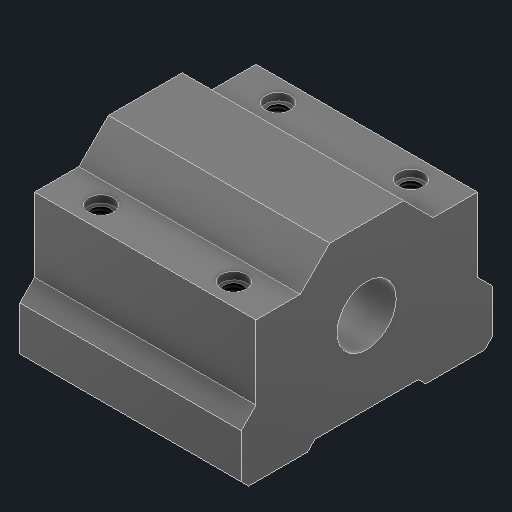
# Autodesk Inventor part: LeadWay
Saved by Autodesk Inventor 2026.2 (Build 302298000, 298)
## iProperties
Created: 2025-11-15
Part Number: LeadWay
Material: ABS 플라스틱
Document SubType Name: Modeling
Designer: work
Density: 1.06 g/cm^3
Appearance: 매끄러움 - 검은색
Author: work
Autodesk Inventor part; units mm, degrees
ref_plane "YZ Plane" through (0, 0, 0) normal (1, 0, 0) x (0, 1, 0)
ref_plane "XZ Plane" through (0, 0, 0) normal (0, 1, 0) x (-1, 0, 0)
ref_plane "XY Plane" through (0, 0, 0) normal (0, 0, 1) x (1, 0, 0)
sketch "스케치1" plane through (0, 0, 0) normal (1, 0, 0) x (0, 1, 0)
  line L0 (0, 0) -> (22, 0) construction
  line L1 (0, 0) -> (0, -17)
  line L2 (0, -17) -> (6, -17)
  line L3 (6, -17) -> (8, -15)
  line L4 (8, -15) -> (18, -15)
  line L5 (18, -15) -> (18, -9)
  line L6 (18, -9) -> (22, -5)
  line L7 (22, -5) -> (22, 0)
  circle A0 centre (11, 0) radius 4
  line L8 (18, -12) -> (0, -12) construction
  line L9 (0, -7) -> (-1, -8)
  line L10 (-1, -8) -> (-1, -16)
  line L11 (-1, -16) -> (0, -17)
  line L12 (-1, -12) -> (0, -12) construction
  line L13 (0, 0) -> (0, 17)
  line L14 (0, 17) -> (6, 17)
  line L15 (6, 17) -> (8, 15)
  line L16 (8, 15) -> (18, 15)
  line L17 (18, 15) -> (18, 9)
  line L18 (18, 9) -> (22, 5)
  line L19 (22, 5) -> (22, 0)
  line L20 (18, 12) -> (0, 12) construction
  line L21 (0, 7) -> (-1, 8)
  line L22 (-1, 8) -> (-1, 16)
  line L23 (-1, 16) -> (0, 17)
  line L24 (-1, 12) -> (0, 12) construction
  point P0 (22, -2.5)
  dimension "d0" = 22
  dimension "d1" = 6
  dimension "d2" = 8
  dimension "d3" = 18
  dimension "d4" = 8
  dimension "d5" = 17
  dimension "d6" = 5
  dimension "d7" = 135
  dimension "d8" = 135
  dimension "d9" = 45
  dimension "d10" = 45
  dimension "d11" = 1
  constraints: 50 end point, 12 symmetric about line, 4 midpoint, 4 perpendicular, 4 point on line, 3 vertical, 1 centre point, 1 horizontal, 1 parallel
  measures "d0" distance of L0.start L0.end
  measures "d1" distance of L1.end L2.end
  measures "d2" horizontal distance of L1.end L3.end
  measures "d3" distance between parallel lines of L1 L5
  measures "d4" diameter of A0
  measures "d5" distance of L0.start L1.end
  measures "d6" distance between parallel lines of L2 L8
  measures "d7" angle of L7 L6
  measures "d8" angle of L2 L3
  measures "d9" angle of L1 L9
  measures "d10" angle of L1 L11
  measures "d11" distance between parallel lines of L1 L10
extrude "돌출1" add sketch "스케치1" along normal blind 30
sketch "스케치2" plane through (0, 18, 15) normal (0, 1, 0) x (1, 0, 0)
  line L0 (0, 6) -> (0, 0) projected
  line L1 (0, 0) -> (30, 0) projected
  line L2 (30, 6) -> (30, 0) projected
  line L3 (0, 6) -> (30, 6) projected
  line L4 (0, 30) -> (0, 24) projected
  line L5 (0, 24) -> (30, 24) projected
  line L6 (30, 30) -> (30, 24) projected
  line L7 (0, 30) -> (30, 30) projected
  line L8 (0, 3) -> (30, 3) construction
  line L9 (0, 15) -> (30, 15)
  point P0 (6, 3)
  point P1 (24, 3)
  point P2 (6, 27)
  point P3 (24, 27)
  dimension "d14" = 18
  dimension "d15" = 6
  constraints: 4 end point, 2 midpoint, 2 point on line, 2 symmetric about line, 1 horizontal
  measures "d14" distance of point (6, 3) point (24, 3)
  measures "d15" distance from line of L0 point (6, 3)
hole "구멍1" at (6, 18, 12) at (24, 18, 12) at (6, 18, -12) at (24, 18, -12) direction (0, -1, 0) diameter 2.459 end through all counterbore diameter 3.4 counterbore depth 1 thread size "M3x0.5" class "6H" standard "ISO Metric profile"
